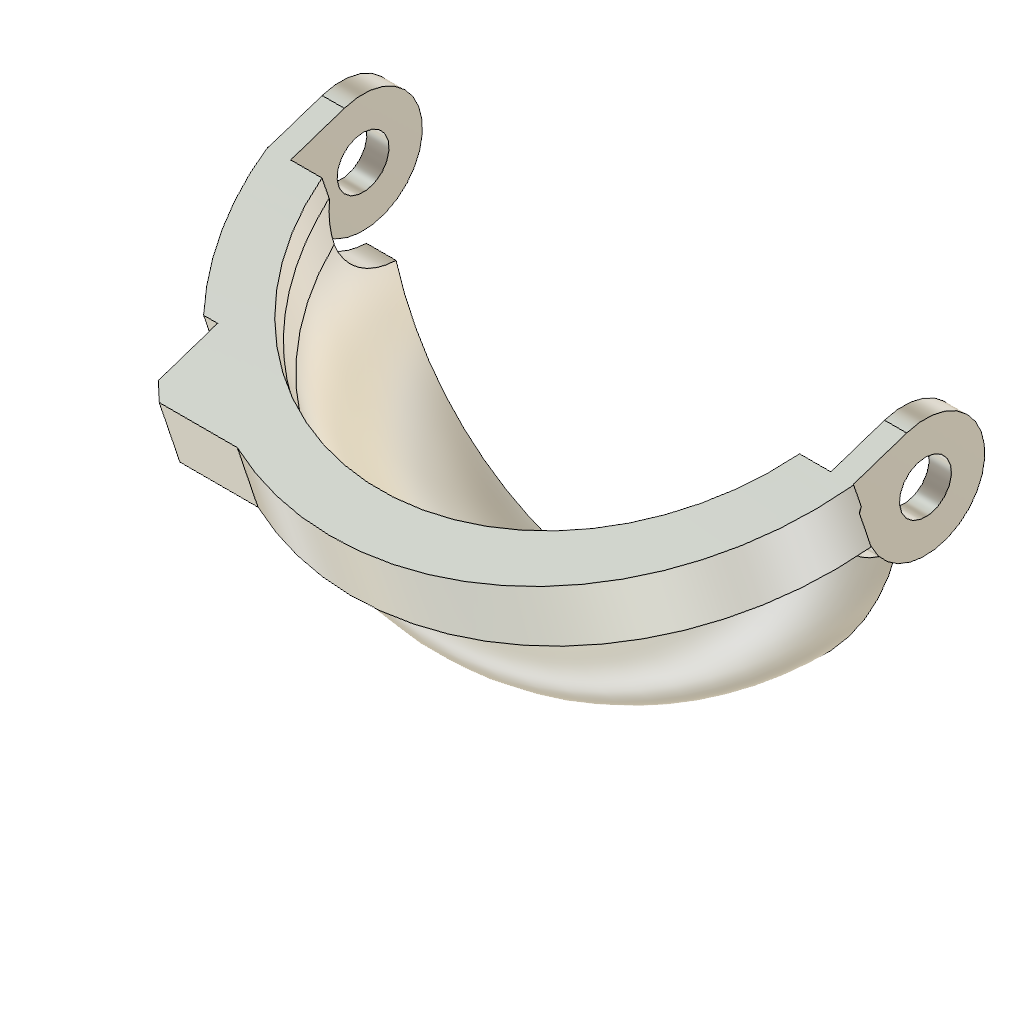
Bottom Left Lid native (Autodesk Fusion 360 design; units mm, degrees)
part number: 2026-10-13-23-16-32-167
Autodesk Fusion 360 part; units mm, degrees
ref_plane "WorkPlane1" through (0, 0, 1.5171) normal (0, 0, 1) x (1, 0, 0)
sketch "Ring A" plane through (0, 0, 1.5171) normal (0, 0, 1) x (1, 0, 0)
  line L0 (-16.5, -0.094) -> (-19.8423, -0.094)
  arc A0 (-19.8423, -0.094) -> (19.8423, -0.094) centre (0, -0.094) ccw
  line L1 (19.8423, -0.094) -> (16.5, -0.094)
  arc A1 (-16.5, -0.094) -> (16.5, -0.094) centre (0, -0.094) ccw
  dimension "d52" = 19.8423
  dimension "d53" = 16.5
  dimension "d54" = 0.094
  dimension "d55" = 16.5
  dimension "d56" = 19.8423
  constraint horizontal L0
  constraint horizontal L1
  constraint coincident A0.centre A1.centre
  constraint vertical origin A0.centre
  measures "d52" radius of A0
  measures "d53" radius of A1
  measures "d54" vertical distance of origin A0.centre
  measures "d55" horizontal distance of origin L0.start
  measures "d56" horizontal distance of origin A0.end
extrude "Ring A (1)" add sketch "Ring A" along normal mid plane 2.9658
ref_plane "WorkPlane2" through (0, -0.094, 0) normal (0, 1, 0) x (0, 0, 1)
sketch "Shell" plane through (0, -0.094, 0) normal (0, 1, 0) x (1, 0, 0)
  line L0 (16.5, -0.5342) -> (18.435, -0.5342)
  line L1 (18.435, -0.5342) -> (18.435, -0.0342)
  arc A0 (18.435, -0.0342) -> (0, 18.4008) centre (0, -0.0342) ccw
  line L2 (0, 18.4008) -> (0, 16.4658)
  arc A1 (16.5, -0.0342) -> (0, 16.4658) centre (0, -0.0342) ccw
  line L3 (16.5, -0.0342) -> (16.5, -0.5342)
  line L4 (0, 18.4008) -> (0, -0.5342) construction
  dimension "d57" = 18.435
  dimension "d58" = 16.5
  dimension "d59" = 0.0342
  dimension "d60" = 0.5342
  dimension "d61" = 18.4008
  dimension "d62" = 0.5342
  constraint horizontal L0
  constraint vertical L1
  constraint vertical L2
  constraint vertical L3
  constraint vertical L4
  constraint tangent L1 A0
  constraint tangent A1 L3
  constraint coincident A0.centre A1.centre
  constraint vertical origin A0.centre
  constraint vertical origin A0.end
  measures "d57" radius of A0
  measures "d58" radius of A1
  measures "d59" vertical distance of origin A0.centre
  measures "d60" vertical distance of origin L0.start
  measures "d61" vertical distance of origin A0.end
  measures "d62" vertical distance of origin L4.end
revolve "Shell (1)" add sketch "Shell" angle 360 about axis through (0, -0.094, -18.4008) along (0, 0, 1)
move_body "Shell to lip frame" bodies 1 to x (1, 0, 0) y (0, 0.999647, 0.026586) z (0, -0.026586, 0.999647) at (0, 0, 0)
ref_plane "WorkPlane3" through (0, 0, 1.7955) normal (0, 0, 1) x (1, 0, 0)
sketch "Ring B" plane through (0, 0, 1.7955) normal (0, 0, 1) x (1, 0, 0)
  line L0 (16.502, -0.1528) -> (20.1014, -0.1528)
  arc A0 (-20.1014, -0.1528) -> (20.1014, -0.1528) centre (0, 0) ccw
  line L1 (-20.1014, -0.1528) -> (-16.502, -0.1528)
  arc A1 (-16.502, -0.1528) -> (16.502, -0.1528) centre (0, -0.1528) ccw
  dimension "d63" = 20.102
  dimension "d64" = 16.502
  dimension "d65" = 0.1528
  dimension "d66" = 16.502
  dimension "d67" = 20.1014
  constraint horizontal L0
  constraint horizontal L1
  constraint coincident A0.centre origin
  constraint vertical A0.centre A1.centre
  measures "d63" radius of A0
  measures "d64" radius of A1
  measures "d65" vertical distance of A0.centre A1.centre
  measures "d66" horizontal distance of A0.centre L0.start
  measures "d67" horizontal distance of A0.centre A0.start
extrude "Ring B (1)" add sketch "Ring B" along normal mid plane 4.409
sketch "Shell trim y-0.1" plane through (0, 0, 0) normal (1, 0, 0) x (0, 0, -1)
  line L0 (25, -8.4589) -> (-25, 8.2481)
  line L1 (-25, 8.2481) -> (-25, 30)
  line L2 (-25, 30) -> (25, 30)
  line L3 (25, 30) -> (25, -8.4589)
  dimension "d68" = 25
  dimension "d69" = 8.4589
  dimension "d70" = 25
  dimension "d71" = 8.2481
  dimension "d72" = 30
  constraint vertical L1
  constraint horizontal L2
  constraint vertical L3
  measures "d68" horizontal distance of origin L0.start
  measures "d69" vertical distance of origin L0.start
  measures "d70" horizontal distance of origin L0.end
  measures "d71" vertical distance of origin L0.end
  measures "d72" vertical distance of origin L1.end
extrude "Shell trim y-0.1 (1)" cut sketch "Shell trim y-0.1" along normal mid plane 42
sketch "Pivot clearance" plane through (0, 0, 0) normal (1, 0, 0) x (0, 0, -1)
  line L0 (-2.3996, -3.8068) -> (-4.5, -3.8068)
  line L1 (-4.5, -3.8068) -> (-4.5, 21)
  line L2 (-4.5, 21) -> (21, 21)
  line L3 (21, 21) -> (21, 0)
  line L4 (21, 0) -> (4.5, 0)
  arc A0 (-2.3996, -3.8068) -> (4.5, 0) centre (0, 0) ccw
  dimension "d73" = 4.5
  dimension "d74" = 2.3996
  dimension "d75" = 4.5
  dimension "d76" = 21
  dimension "d77" = 21
  constraint horizontal L0
  constraint vertical L1
  constraint horizontal L2
  constraint vertical L3
  constraint horizontal L4
  constraint coincident A0.centre origin
  constraint horizontal A0.centre L3.end
  measures "d73" radius of A0
  measures "d74" horizontal distance of A0.centre L0.start
  measures "d75" horizontal distance of A0.centre L0.end
  measures "d76" vertical distance of A0.centre L1.end
  measures "d77" horizontal distance of A0.centre L2.end
extrude "Pivot clearance (1)" cut sketch "Pivot clearance" along normal mid plane 36.4
ref_plane "WorkPlane4" through (20.35, 0, 0) normal (1, 0, 0) x (0, 1, 0)
sketch "Past ear R" plane through (20.35, 0, 0) normal (1, 0, 0) x (0, 0, -1)
  line L0 (-2.3996, -3.8068) -> (-4.5, -3.8068)
  line L1 (-4.5, -3.8068) -> (-4.5, 21)
  line L2 (-4.5, 21) -> (21, 21)
  line L3 (21, 21) -> (21, 0)
  line L4 (21, 0) -> (4.5, 0)
  arc A0 (-2.3996, -3.8068) -> (4.5, 0) centre (0, 0) ccw
  dimension "d78" = 4.5
  dimension "d79" = 2.3996
  dimension "d80" = 4.5
  dimension "d81" = 21
  dimension "d82" = 21
  constraint horizontal L0
  constraint vertical L1
  constraint horizontal L2
  constraint vertical L3
  constraint horizontal L4
  constraint coincident A0.centre origin
  constraint horizontal A0.centre L3.end
  measures "d78" radius of A0
  measures "d79" horizontal distance of A0.centre L0.start
  measures "d80" horizontal distance of A0.centre L0.end
  measures "d81" vertical distance of A0.centre L1.end
  measures "d82" horizontal distance of A0.centre L2.end
extrude "Past ear R (1)" cut sketch "Past ear R" along normal mid plane 1.3
ref_plane "WorkPlane5" through (-20.35, 0, 0) normal (1, 0, 0) x (0, 1, 0)
sketch "Past ear L" plane through (-20.35, 0, 0) normal (1, 0, 0) x (0, 0, -1)
  line L0 (-2.3996, -3.8068) -> (-4.5, -3.8068)
  line L1 (-4.5, -3.8068) -> (-4.5, 21)
  line L2 (-4.5, 21) -> (21, 21)
  line L3 (21, 21) -> (21, 0)
  line L4 (21, 0) -> (4.5, 0)
  arc A0 (-2.3996, -3.8068) -> (4.5, 0) centre (0, 0) ccw
  dimension "d83" = 4.5
  dimension "d84" = 2.3996
  dimension "d85" = 4.5
  dimension "d86" = 21
  dimension "d87" = 21
  constraint horizontal L0
  constraint vertical L1
  constraint horizontal L2
  constraint vertical L3
  constraint horizontal L4
  constraint coincident A0.centre origin
  constraint horizontal A0.centre L3.end
  measures "d83" radius of A0
  measures "d84" horizontal distance of A0.centre L0.start
  measures "d85" horizontal distance of A0.centre L0.end
  measures "d86" vertical distance of A0.centre L1.end
  measures "d87" horizontal distance of A0.centre L2.end
extrude "Past ear L (1)" cut sketch "Past ear L" along normal mid plane 1.3
ref_plane "WorkPlane6" through (18.95, 0, 0) normal (1, 0, 0) x (0, 1, 0)
sketch "Ear R" plane through (18.95, 0, 0) normal (1, 0, 0) x (0, 0, -1)
  line L0 (-4, -4) -> (0.409, -4)
  line L1 (0.409, -4) -> (0.409, -3.979)
  arc A0 (0.409, -3.979) -> (-4, 0) centre (0, 0) ccw
  line L2 (-4, 0) -> (-4, -4)
  dimension "d88" = 4
  dimension "d89" = 4
  dimension "d90" = 0.409
  constraint horizontal L0
  constraint vertical L1
  constraint vertical L2
  constraint tangent A0 L2
  constraint coincident A0.centre origin
  measures "d88" radius of A0
  measures "d89" vertical distance of A0.centre L0.start
  measures "d90" horizontal distance of A0.centre L0.end
extrude "Ear R (1)" add sketch "Ear R" along normal mid plane 1.5
ref_plane "WorkPlane7" through (-18.95, 0, 0) normal (1, 0, 0) x (0, 1, 0)
sketch "Ear L" plane through (-18.95, 0, 0) normal (1, 0, 0) x (0, 0, -1)
  line L0 (-4, -4) -> (0.409, -4)
  line L1 (0.409, -4) -> (0.409, -3.979)
  arc A0 (0.409, -3.979) -> (-4, 0) centre (0, 0) ccw
  line L2 (-4, 0) -> (-4, -4)
  dimension "d91" = 4
  dimension "d92" = 4
  dimension "d93" = 0.409
  constraint horizontal L0
  constraint vertical L1
  constraint vertical L2
  constraint tangent A0 L2
  constraint coincident A0.centre origin
  measures "d91" radius of A0
  measures "d92" vertical distance of A0.centre L0.start
  measures "d93" horizontal distance of A0.centre L0.end
extrude "Ear L (1)" add sketch "Ear L" along normal mid plane 1.5
ref_plane "WorkPlane8" through (18.95, 0, 0) normal (1, 0, 0) x (0, 1, 0)
sketch "Ear hole R" plane through (18.95, 0, 0) normal (1, 0, 0) x (0, 0, -1)
  circle A0 centre (0, 0) radius 1.75
  dimension "d94" = 3.5
  constraint coincident A0.centre origin
  measures "d94" diameter of A0
extrude "Ear hole R (1)" cut sketch "Ear hole R" along normal mid plane 2.5
ref_plane "WorkPlane9" through (-18.95, 0, 0) normal (1, 0, 0) x (0, 1, 0)
sketch "Ear hole L" plane through (-18.95, 0, 0) normal (1, 0, 0) x (0, 0, -1)
  circle A0 centre (0, 0) radius 1.75
  dimension "d95" = 3.5
  constraint coincident A0.centre origin
  measures "d95" diameter of A0
extrude "Ear hole L (1)" cut sketch "Ear hole L" along normal mid plane 2.5
ref_plane "WorkPlane10" through (0, 0, 1.7955) normal (0, 0, 1) x (1, 0, 0)
sketch "Tab notch" plane through (0, 0, 1.7955) normal (0, 0, 1) x (1, 0, 0)
  line L0 (-14.1348, -13.2933) -> (-14.1348, -21)
  line L1 (-14.1348, -21) -> (-21, -21)
  line L2 (-21, -21) -> (-21, -13.2933)
  line L3 (-21, -13.2933) -> (-14.1348, -13.2933)
  dimension "d96" = 14.1348
  dimension "d97" = 13.2933
  dimension "d98" = 21
  dimension "d99" = 21
  constraint vertical L0
  constraint horizontal L1
  constraint vertical L2
  constraint horizontal L3
  measures "d96" horizontal distance of origin L0.start
  measures "d97" vertical distance of origin L0.start
  measures "d98" vertical distance of origin L0.end
  measures "d99" horizontal distance of origin L1.end
extrude "Tab notch (1)" cut sketch "Tab notch" along normal mid plane 5.409
ref_plane "WorkPlane11" through (0, 0, 1.7955) normal (0, 0, 1) x (1, 0, 0)
sketch "Tab" plane through (0, 0, 1.7955) normal (0, 0, 1) x (1, 0, 0)
  line L0 (-14.1348, -13.2933) -> (-6, -18.5)
  line L1 (-6, -18.5) -> (-13.1348, -18.5)
  line L2 (-13.1348, -18.5) -> (-14.1348, -17.5)
  line L3 (-14.1348, -17.5) -> (-14.1348, -13.2933)
  dimension "d100" = 14.1348
  dimension "d101" = 13.2933
  dimension "d102" = 6
  dimension "d103" = 18.5
  dimension "d104" = 13.1348
  dimension "d105" = 17.5
  constraint horizontal L1
  constraint vertical L3
  measures "d100" horizontal distance of origin L0.start
  measures "d101" vertical distance of origin L0.start
  measures "d102" horizontal distance of origin L0.end
  measures "d103" vertical distance of origin L0.end
  measures "d104" horizontal distance of origin L1.end
  measures "d105" vertical distance of origin L2.end
extrude "Tab (1)" add sketch "Tab" along normal mid plane 4.409
ref_plane "WorkPlane12" through (-11.3848, 0, 0) normal (1, 0, 0) x (0, 1, 0)
sketch "Tab pin hole" plane through (-11.3848, 0, 0) normal (1, 0, 0) x (0, 0, -1)
  circle A0 centre (-1.7955, -16) radius 1
  dimension "d106" = 2
  dimension "d107" = 1.7955
  dimension "d108" = 16
  measures "d106" diameter of A0
  measures "d107" horizontal distance of origin A0.centre
  measures "d108" vertical distance of origin A0.centre
extrude "Tab pin hole (1)" cut sketch "Tab pin hole" along normal mid plane 6.5
move_body "Frame x +18.4765 deg" bodies 1 to x (1, 0, 0) y (0, 0.948453, 0.316917) z (0, -0.316917, 0.948453) at (0, 0, 0)
named bodies: "Bottom Left Lid native"
